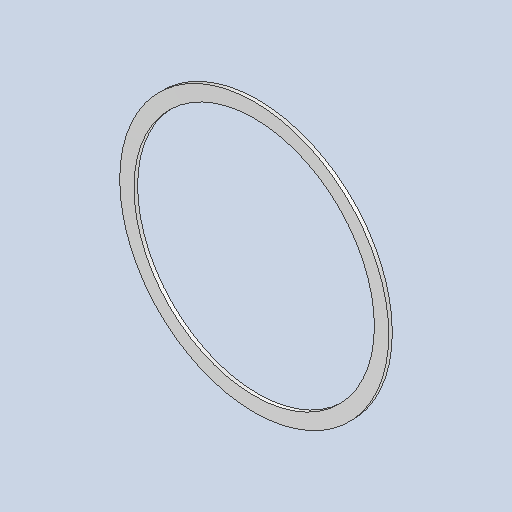
# Autodesk Inventor part: DMF-1212 Gear Ring 03
Saved by Autodesk Inventor 2026.2 (Build 302298000, 298)
## iProperties
Created: 2024-04-30
Part Number: DMF-1212 Gear Ring 03
Material: Stainless Steel AISI 304
Document SubType Name: Sheet Metal
Designer: admin
Stock Number: DMF-1212
Density: 8 g/cm^3
Flat Pattern Width: 15 cm
Flat Pattern Length: 15 cm
Flat Pattern Area: 225 cm^2
Sheet Metal Rule: Default
Sheet Metal Width: 150,000 mm
Sheet Metal Length: 150,000 mm
Sheet Metal Area: 22500,000 mm^2
Appearance: Chrome - Satin
Mass: 16.575 g
Surface Area: 188.37 cm^2
Volume: 16.575 cm^3
Author: pokla
Autodesk Inventor part; units mm, degrees
ref_plane "YZ Plane" through (0, 0, 0) normal (1, 0, 0) x (0, 1, 0)
ref_plane "XZ Plane" through (0, 0, 0) normal (0, 1, 0) x (-1, 0, 0)
ref_plane "XY Plane" through (0, 0, 0) normal (0, 0, 1) x (1, 0, 0)
sketch "Sketch1" plane through (0, 0, 0) normal (0, 0, 1) x (1, 0, 0)
  circle A0 centre (0, 0) radius 67
  circle A1 centre (0, 0) radius 75
  line L0 (0, 0) -> (0, 67) construction
  line L1 (0, 0) -> (-75, 0) construction
  circle A2 centre (29.658, 71.6007) radius 3.5 construction
  line L2 (29.658, 71.6007) -> (0, 0) construction
  circle A3 centre (0, 0) radius 77.5 construction
  circle A4 centre (-29.658, 71.6007) radius 3.5 construction
  circle A5 centre (-71.6007, 29.658) radius 3.5 construction
  circle A6 centre (-71.6007, -29.658) radius 3.5 construction
  circle A7 centre (-29.658, -71.6007) radius 3.5 construction
  circle A8 centre (29.658, -71.6007) radius 3.5 construction
  circle A9 centre (71.6007, -29.658) radius 3.5 construction
  circle A10 centre (71.6007, 29.658) radius 3.5 construction
  point P0 (0, -75)
  dimension "d32" = 134
  dimension "d97" = 155
  dimension "d31" = 150
  dimension "d95" = 7
  dimension "d96" = 22.5
  dimension "d100" = 360
  measures "d31" diameter of A1
  measures "d95" diameter of A2
  measures "d96" angle of L2 L0
extrude "Plate4" add sketch "Sketch1" along normal blind 2
equation "\"d63\" = Thickness"
equation "\"BendRadius\" = Thickness"
equation "\"BendReliefWidth\" = Thickness"
equation "\"BendReliefDepth\" = 0.5 * Thickness"
equation "\"CornerReliefSize\" = 4 * Thickness"
equation "\"MinimumRemnant\" = 2 * Thickness"
equation "\"TransitionRadius\" = BendRadius"
equation "\"JacobiRadiusSize\" = BendRadius"
equation "\"GapSize\" = Thickness"
equation "\"Thickness\" = 2"
body "Solid3"
